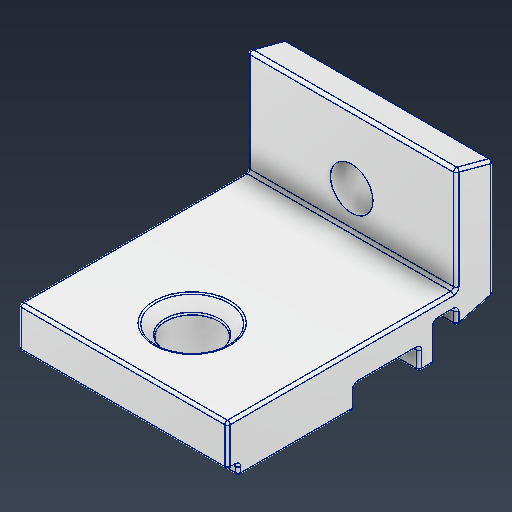
# Autodesk Inventor part: 2020 Panel Bracket
Saved by Autodesk Inventor 2026.2 (Build 302298010, 298A)
## iProperties
Created: 2026-05-13
Part Number: 2020 Panel Bracket
Material: 알루미늄 6061
Document SubType Name: Modeling
Designer: khw
Density: 2.7 g/cm^3
Appearance: 알루미늄 - 평지
Author: khw
Autodesk Inventor part; units mm, degrees
ref_plane "YZ Plane" through (0, 0, 0) normal (1, 0, 0) x (0, 1, 0)
ref_plane "XZ Plane" through (0, 0, 0) normal (0, 1, 0) x (-1, 0, 0)
ref_plane "XY Plane" through (0, 0, 0) normal (0, 0, 1) x (1, 0, 0)
sketch "스케치1" plane through (0, 0, 0) normal (1, 0, 0) x (0, 1, 0)
  line L0 (0, 0) -> (14.8, 0)
  line L1 (14.8, 0) -> (14.8, -25)
  line L2 (14.8, -25) -> (0, -25)
  line L3 (0, -25) -> (0, 0)
  line L4 (4.9, 0) -> (4.9, -21.5)
  line L5 (4.9, -21.5) -> (14.8, -21.5)
  line L6 (14.8, -21.5) -> (13.8622, -25)
  line L7 (8.35, -21.5) -> (8.35, -25) construction
  line L8 (3.4, -19.5) -> (3.4, -21.5)
  line L9 (3.4, -21.5) -> (1.9, -21.5)
  line L10 (3.4, -19.5) -> (0, -19.5)
  line L11 (0, -18) -> (2, -18)
  line L12 (2, -18) -> (2, -12)
  line L13 (2, -12) -> (0, -12)
  line L14 (1, 0) -> (1, -1)
  line L15 (1, -1) -> (0, -1)
  line L16 (1.9, -21.5) -> (2.8378, -25)
  point P0 (9.85, -21.5)
  dimension "d0" = 25
  dimension "d1" = 2.9
  dimension "d2" = 4.9
  dimension "d3" = 1.5
  dimension "d4" = 75
  dimension "d5" = 3.5
  dimension "d7" = 1.5
  dimension "d8" = 1.5
  dimension "d9" = 1
  dimension "d10" = 1
  dimension "d11" = 2
  dimension "d12" = 6
  dimension "d13" = 12.9
  constraints: 34 end point, 10 point on line, 7 perpendicular, 3 horizontal, 3 vertical, 2 parallel, 2 symmetric about line, 1 midpoint
  measures "d0" distance of L0.end L1.end
  measures "d1" distance between parallel lines of L4 L12
  measures "d2" distance between parallel lines of L3 L4
  measures "d3" distance between parallel lines of L4 L8
  measures "d4" angle of L16 L5
  measures "d5" distance from line of L2 point (9.85, -21.5)
  measures "d7" distance of L9.end L8.end
  measures "d8" distance between parallel lines of L10 L11
  measures "d9" distance of L14.start L14.end
  measures "d10" distance of L14.end L15.end
  measures "d11" distance of L8.start L8.end
  measures "d12" distance of L11.end L12.end
  measures "d13" distance of L5.end L9.end
extrude "돌출1" add sketch "스케치1" along normal blind 19.64 contours L0 L4 L5 L6 L2 L16 L9 L8 L10 L3 L11 L12 L13 L15 L14
sketch "스케치2" plane through (0, 0, -12) normal (0, -1, 0) x (1, 0, 0)
  line L0 (0, 11) -> (0, 0) projected
  line L1 (0, 0) -> (19.64, 0) projected
  line L2 (19.64, 11) -> (19.64, 0) projected
  line L3 (0, 11) -> (19.64, 11) projected
  line L4 (19.64, 5.5) -> (0, 5.5) construction
  circle A0 centre (9.82, 5.5) radius 2.5
  point P0 (0, 12)
  dimension "d16" = 5
  constraints: 3 midpoint, 2 end point, 1 centre point
  measures "d16" diameter of A0
extrude "돌출2" cut sketch "스케치2" against normal through all contours A0
chamfer "모따기1" distance 1 angle 45 1 edges at (7.32, 4.9, -6.5)
fillet "모깎기1" radius 0.25 51 edges at (9.82, 0, -12) (0, 4.9, -10.75) (19.64, 4.9, -10.75) (7.32, 3.9, -6.5) (6.32, 4.9, -6.5) (7.32, 0, -6.5) (19.64, 0, -6.5) (9.82, 4.9, 0) (9.82, 0, -1) (19.64, 0.5, -1) (19.64, 2.95, 0) (9.82, 1, 0) (19.64, 1, -0.5) (9.82, 1, -1) (0, 0, -6.5) (0, 0.5, -1) (0, 2.95, 0) (0, 1, -0.5) (0, 14.3311, -23.25) (0, 9.85, -21.5) (9.82, 4.9, -21.5) (0, 2.3689, -23.25) (19.64, 2.3689, -23.25) (9.82, 2.8378, -25) (19.64, 9.85, -21.5) (0, 8.35, -25) (19.64, 8.35, -25) (9.82, 13.8622, -25) (19.64, 14.3311, -23.25) (9.82, 14.8, -21.5) (19.64, 1, -12) (0, 1, -12) (19.64, 2, -15) (0, 2, -15) (9.82, 2, -18) (19.64, 1, -18) (9.82, 0, -18) (19.64, 1.7, -19.5) (0, 1.7, -19.5) (19.64, 0, -18.75) (0, 0, -18.75) (9.82, 0, -19.5) (0, 1, -18) (9.82, 2, -12) (19.64, 3.4, -20.5) (0, 3.4, -20.5) (9.82, 3.4, -21.5) (19.64, 2.65, -21.5) (9.82, 1.9, -21.5) (0, 2.65, -21.5) (9.82, 3.4, -19.5)
sketch "스케치3" plane through (19.39, 13.6703, -25) normal (0, 0, -1) x (-1, 0, 0)
  line L0 (19.14, 0) -> (19.14, -10.6407) projected
  line L1 (0, 0) -> (19.14, 0) projected
  line L2 (0, -10.6407) -> (0, 0) projected
  line L3 (19.14, -10.6407) -> (0, -10.6407) projected
  line L4 (19.14, -5.3203) -> (0, -5.3203) construction
  circle A0 centre (9.57, -5.3203) radius 2
  point P0 (19.39, -13.6703)
  dimension "d23" = 4
  constraints: 3 midpoint, 2 end point, 1 centre point
  measures "d23" diameter of A0
extrude "돌출3" cut sketch "스케치3" against normal through all contours A0
